Autodesk Fusion 360 part; units mm, degrees
(part 2 of 11)
  spline S15 degree 5 poles (4.403, 16.2127) (4.3927, 16.2052) (4.3722, 16.19) (4.3414, 16.1671) (4.3006, 16.1365) (4.2499, 16.098) (4.1996, 16.0592) (4.1496, 16.0202) (4.0999, 15.981) (4.0506, 15.9416) (4.0017, 15.9019) (3.9531, 15.8619) (3.9049, 15.8218) (3.857, 15.7814) (3.8095, 15.7408) (3.7624, 15.7) (3.7156, 15.6589) (3.6692, 15.6176) (3.6232, 15.5761) (3.5775, 15.5343) (3.5323, 15.4924) (3.4874, 15.4502) (3.443, 15.4078) (3.3989, 15.3651) (3.3552, 15.3223) (3.3119, 15.2792) (3.2691, 15.2359) (3.2266, 15.1924) (3.1846, 15.1487) (3.1429, 15.1048) (3.1017, 15.0607) (3.061, 15.0163) (3.0206, 14.9718) (2.9807, 14.927) (2.9412, 14.882) (2.9022, 14.8369) (2.8637, 14.7915) (2.8255, 14.7459) (2.7879, 14.7001) (2.7507, 14.6541) (2.714, 14.6079) (2.6778, 14.5615) (2.642, 14.5149) (2.6068, 14.4681) (2.5721, 14.4211) (2.5379, 14.3739) (2.5042, 14.3265) (2.471, 14.2789) (2.4383, 14.2311) (2.4062, 14.1831) (2.3746, 14.1349) (2.3436, 14.0866) (2.3132, 14.038) (2.2835, 13.9892) (2.2544, 13.9402) (2.2259, 13.891) (2.1979, 13.8417) (2.1705, 13.7921) (2.1437, 13.7424) (2.1175, 13.6925) (2.0921, 13.6424) (2.0677, 13.5921) (2.0442, 13.5415) (2.0218, 13.4906) (2.0002, 13.4395) (1.9793, 13.3882) (1.9589, 13.3369) (1.939, 13.2854) (1.9198, 13.2338) (1.9019, 13.1819) (1.8859, 13.1297) (1.8754, 13.0874) (1.8691, 13.0553) (1.8657, 13.0338) (1.8641, 13.023) knots -1 -1 -1 -1 -1 -1 -0.98571429 -0.97142857 -0.95714286 -0.94285714 -0.92857143 -0.91428571 -0.9 -0.88571429 -0.87142857 -0.85714286 -0.84285714 -0.82857143 -0.81428571 -0.8 -0.78571429 -0.77142857 -0.75714286 -0.74285714 -0.72857143 -0.71428571 -0.7 -0.68571429 -0.67142857 -0.65714286 -0.64285714 -0.62857143 -0.61428571 -0.6 -0.58571429 -0.57142857 -0.55714286 -0.54285714 -0.52857143 -0.51428571 -0.5 -0.48571429 -0.47142857 -0.45714286 -0.44285714 -0.42857143 -0.41428571 -0.4 -0.38571429 -0.37142857 -0.35714286 -0.34285714 -0.32857143 -0.31428571 -0.3 -0.28571429 -0.27142857 -0.25714286 -0.24285714 -0.22857143 -0.21428571 -0.2 -0.18571429 -0.17142857 -0.15714286 -0.14285714 -0.12857143 -0.11428571 -0.1 -0.08571429 -0.07142857 -0.05714286 -0.04285714 -0.02857143 -0.01428571 0 0 0 0 0 0
  line L15 (1.8641, 13.023) -> (1.6349, 11.4289)
  arc A31 (0.5894, 10.5728) -> (1.6349, 11.4289) centre (0.6451, 11.5712) ccw
  arc A32 (0.5894, 10.5728) -> (-0.5894, 10.5728) centre (0, 0) ccw
  arc A33 (-1.6349, 11.4289) -> (-0.5894, 10.5728) centre (-0.6451, 11.5712) ccw
  line L16 (-1.6349, 11.4289) -> (-1.8641, 13.023)
  spline S16 degree 5 poles (-1.8641, 13.023) (-1.8657, 13.0338) (-1.8691, 13.0553) (-1.8754, 13.0874) (-1.8859, 13.1297) (-1.9019, 13.1819) (-1.9198, 13.2338) (-1.939, 13.2854) (-1.9589, 13.3369) (-1.9793, 13.3882) (-2.0002, 13.4395) (-2.0218, 13.4906) (-2.0442, 13.5415) (-2.0677, 13.5921) (-2.0921, 13.6424) (-2.1175, 13.6925) (-2.1437, 13.7424) (-2.1705, 13.7921) (-2.1979, 13.8417) (-2.2259, 13.891) (-2.2544, 13.9402) (-2.2835, 13.9892) (-2.3132, 14.038) (-2.3436, 14.0866) (-2.3746, 14.1349) (-2.4062, 14.1831) (-2.4383, 14.2311) (-2.471, 14.2789) (-2.5042, 14.3265) (-2.5379, 14.3739) (-2.5721, 14.4211) (-2.6068, 14.4681) (-2.642, 14.5149) (-2.6778, 14.5615) (-2.714, 14.6079) (-2.7507, 14.6541) (-2.7879, 14.7001) (-2.8255, 14.7459) (-2.8637, 14.7915) (-2.9022, 14.8369) (-2.9412, 14.882) (-2.9807, 14.927) (-3.0206, 14.9718) (-3.061, 15.0163) (-3.1017, 15.0607) (-3.1429, 15.1048) (-3.1846, 15.1487) (-3.2266, 15.1924) (-3.2691, 15.2359) (-3.3119, 15.2792) (-3.3552, 15.3223) (-3.3989, 15.3651) (-3.443, 15.4078) (-3.4874, 15.4502) (-3.5323, 15.4924) (-3.5775, 15.5343) (-3.6232, 15.5761) (-3.6692, 15.6176) (-3.7156, 15.6589) (-3.7624, 15.7) (-3.8095, 15.7408) (-3.857, 15.7814) (-3.9049, 15.8218) (-3.9531, 15.8619) (-4.0017, 15.9019) (-4.0506, 15.9416) (-4.0999, 15.981) (-4.1496, 16.0202) (-4.1996, 16.0592) (-4.2499, 16.098) (-4.3006, 16.1365) (-4.3414, 16.1671) (-4.3722, 16.19) (-4.3927, 16.2052) (-4.403, 16.2127) knots 0 0 0 0 0 0 0.01428571 0.02857143 0.04285714 0.05714286 0.07142857 0.08571429 0.1 0.11428571 0.12857143 0.14285714 0.15714286 0.17142857 0.18571429 0.2 0.21428571 0.22857143 0.24285714 0.25714286 0.27142857 0.28571429 0.3 0.31428571 0.32857143 0.34285714 0.35714286 0.37142857 0.38571429 0.4 0.41428571 0.42857143 0.44285714 0.45714286 0.47142857 0.48571429 0.5 0.51428571 0.52857143 0.54285714 0.55714286 0.57142857 0.58571429 0.6 0.61428571 0.62857143 0.64285714 0.65714286 0.67142857 0.68571429 0.7 0.71428571 0.72857143 0.74285714 0.75714286 0.77142857 0.78571429 0.8 0.81428571 0.82857143 0.84285714 0.85714286 0.87142857 0.88571429 0.9 0.91428571 0.92857143 0.94285714 0.95714286 0.97142857 0.98571429 1 1 1 1 1 1
  arc A34 (-4.403, 16.2127) -> (-5.9675, 15.7044) centre (0, 0) ccw
  spline S17 degree 5 poles (-5.9675, 15.7044) (-5.9714, 15.6922) (-5.9791, 15.6679) (-5.9905, 15.6313) (-6.0055, 15.5825) (-6.0239, 15.5216) (-6.0419, 15.4606) (-6.0594, 15.3997) (-6.0765, 15.3388) (-6.0932, 15.2779) (-6.1095, 15.217) (-6.1253, 15.1562) (-6.1407, 15.0953) (-6.1557, 15.0345) (-6.1703, 14.9737) (-6.1844, 14.913) (-6.1981, 14.8523) (-6.2113, 14.7916) (-6.2242, 14.731) (-6.2365, 14.6704) (-6.2485, 14.6098) (-6.26, 14.5493) (-6.271, 14.4889) (-6.2816, 14.4285) (-6.2918, 14.3681) (-6.3015, 14.3079) (-6.3107, 14.2476) (-6.3195, 14.1875) (-6.3278, 14.1274) (-6.3357, 14.0674) (-6.3431, 14.0075) (-6.35, 13.9477) (-6.3565, 13.8879) (-6.3624, 13.8282) (-6.3679, 13.7686) (-6.3729, 13.7092) (-6.3775, 13.6498) (-6.3815, 13.5905) (-6.385, 13.5313) (-6.3881, 13.4722) (-6.3906, 13.4133) (-6.3927, 13.3545) (-6.3942, 13.2957) (-6.3952, 13.2372) (-6.3956, 13.1787) (-6.3956, 13.1204) (-6.395, 13.0623) (-6.3938, 13.0043) (-6.3922, 12.9464) (-6.39, 12.8887) (-6.3872, 12.8312) (-6.3839, 12.7738) (-6.3799, 12.7167) (-6.3752, 12.6597) (-6.37, 12.603) (-6.3642, 12.5464) (-6.3578, 12.49) (-6.3508, 12.4339) (-6.3433, 12.3779) (-6.3352, 12.3221) (-6.3262, 12.2667) (-6.3164, 12.2116) (-6.3057, 12.1568) (-6.2939, 12.1025) (-6.2813, 12.0484) (-6.2681, 11.9947) (-6.2544, 11.9412) (-6.2402, 11.8878) (-6.2255, 11.8348) (-6.2095, 11.7823) (-6.1917, 11.7307) (-6.1753, 11.6903) (-6.1615, 11.6606) (-6.1517, 11.6412) (-6.1466, 11.6315) knots -1 -1 -1 -1 -1 -1 -0.98571429 -0.97142857 -0.95714286 -0.94285714 -0.92857143 -0.91428571 -0.9 -0.88571429 -0.87142857 -0.85714286 -0.84285714 -0.82857143 -0.81428571 -0.8 -0.78571429 -0.77142857 -0.75714286 -0.74285714 -0.72857143 -0.71428571 -0.7 -0.68571429 -0.67142857 -0.65714286 -0.64285714 -0.62857143 -0.61428571 -0.6 -0.58571429 -0.57142857 -0.55714286 -0.54285714 -0.52857143 -0.51428571 -0.5 -0.48571429 -0.47142857 -0.45714286 -0.44285714 -0.42857143 -0.41428571 -0.4 -0.38571429 -0.37142857 -0.35714286 -0.34285714 -0.32857143 -0.31428571 -0.3 -0.28571429 -0.27142857 -0.25714286 -0.24285714 -0.22857143 -0.21428571 -0.2 -0.18571429 -0.17142857 -0.15714286 -0.14285714 -0.12857143 -0.11428571 -0.1 -0.08571429 -0.07142857 -0.05714286 -0.04285714 -0.02857143 -0.01428571 0 0 0 0 0 0
  line L17 (-6.1466, 11.6315) -> (-5.3951, 10.2071)
  arc A35 (-5.7377, 8.9) -> (-5.3951, 10.2071) centre (-6.2795, 9.7405) ccw
  arc A36 (-5.7377, 8.9) -> (-6.6914, 8.2071) centre (0, 0) ccw
  arc A37 (-8.0404, 8.2852) -> (-6.6914, 8.2071) centre (-7.3233, 8.9822) ccw
  line L18 (-8.0404, 8.2852) -> (-9.1628, 9.4401)
  spline S18 degree 5 poles (-9.1628, 9.4401) (-9.1704, 9.4479) (-9.1859, 9.4633) (-9.2098, 9.4855) (-9.2432, 9.5136) (-9.2868, 9.5465) (-9.3318, 9.5779) (-9.3777, 9.6084) (-9.424, 9.6383) (-9.4707, 9.6679) (-9.5177, 9.6971) (-9.5652, 9.7257) (-9.6133, 9.7537) (-9.662, 9.7809) (-9.7114, 9.8072) (-9.7614, 9.8328) (-9.8119, 9.8578) (-9.8628, 9.8823) (-9.9141, 9.9062) (-9.9657, 9.9297) (-10.0177, 9.9528) (-10.07, 9.9753) (-10.1228, 9.9973) (-10.1759, 10.0187) (-10.2294, 10.0397) (-10.2833, 10.0601) (-10.3375, 10.08) (-10.392, 10.0994) (-10.4468, 10.1184) (-10.5019, 10.137) (-10.5574, 10.1551) (-10.6131, 10.1727) (-10.6691, 10.1898) (-10.7254, 10.2065) (-10.782, 10.2228) (-10.8388, 10.2386) (-10.8959, 10.2539) (-10.9533, 10.2689) (-11.011, 10.2833) (-11.0688, 10.2974) (-11.127, 10.311) (-11.1853, 10.3242) (-11.2439, 10.337) (-11.3027, 10.3493) (-11.3618, 10.3612) (-11.4211, 10.3727) (-11.4806, 10.3837) (-11.5403, 10.3944) (-11.6002, 10.4046) (-11.6603, 10.4144) (-11.7206, 10.4238) (-11.7812, 10.4328) (-11.8419, 10.4414) (-11.9028, 10.4496) (-11.9639, 10.4573) (-12.0251, 10.4647) (-12.0866, 10.4716) (-12.1482, 10.4782) (-12.21, 10.4843) (-12.272, 10.4901) (-12.3341, 10.4954) (-12.3965, 10.5003) (-12.4589, 10.5049) (-12.5215, 10.509) (-12.5843, 10.5128) (-12.6472, 10.5161) (-12.7103, 10.519) (-12.7735, 10.5216) (-12.8369, 10.5237) (-12.9004, 10.5255) (-12.964, 10.5269) (-13.0151, 10.5277) (-13.0534, 10.5281) (-13.079, 10.5283) (-13.0918, 10.5283) knots 0 0 0 0 0 0 0.01428571 0.02857143 0.04285714 0.05714286 0.07142857 0.08571429 0.1 0.11428571 0.12857143 0.14285714 0.15714286 0.17142857 0.18571429 0.2 0.21428571 0.22857143 0.24285714 0.25714286 0.27142857 0.28571429 0.3 0.31428571 0.32857143 0.34285714 0.35714286 0.37142857 0.38571429 0.4 0.41428571 0.42857143 0.44285714 0.45714286 0.47142857 0.48571429 0.5 0.51428571 0.52857143 0.54285714 0.55714286 0.57142857 0.58571429 0.6 0.61428571 0.62857143 0.64285714 0.65714286 0.67142857 0.68571429 0.7 0.71428571 0.72857143 0.74285714 0.75714286 0.77142857 0.78571429 0.8 0.81428571 0.82857143 0.84285714 0.85714286 0.87142857 0.88571429 0.9 0.91428571 0.92857143 0.94285714 0.95714286 0.97142857 0.98571429 1 1 1 1 1 1
  arc A38 (-13.0918, 10.5283) -> (-14.0586, 9.1976) centre (0, 0) ccw
  spline S19 degree 5 poles (-14.0586, 9.1976) (-14.0546, 9.1854) (-14.0465, 9.1611) (-14.0343, 9.1248) (-14.0178, 9.0765) (-13.9968, 9.0164) (-13.9755, 8.9566) (-13.9539, 8.897) (-13.9319, 8.8377) (-13.9096, 8.7786) (-13.887, 8.7198) (-13.864, 8.6612) (-13.8407, 8.603) (-13.8171, 8.5449) (-13.7932, 8.4872) (-13.7689, 8.4298) (-13.7443, 8.3726) (-13.7194, 8.3157) (-13.6941, 8.2591) (-13.6685, 8.2028) (-13.6426, 8.1468) (-13.6163, 8.0911) (-13.5897, 8.0357) (-13.5628, 7.9806) (-13.5355, 7.9258) (-13.508, 7.8714) (-13.48, 7.8172) (-13.4518, 7.7634) (-13.4232, 7.7099) (-13.3943, 7.6568) (-13.3651, 7.6039) (-13.3355, 7.5514) (-13.3056, 7.4993) (-13.2753, 7.4475) (-13.2448, 7.3961) (-13.2139, 7.345) (-13.1826, 7.2943) (-13.151, 7.244) (-13.1191, 7.194) (-13.0869, 7.1444) (-13.0543, 7.0952) (-13.0213, 7.0465) (-12.988, 6.9981) (-12.9544, 6.9501) (-12.9204, 6.9026) (-12.8861, 6.8554) (-12.8515, 6.8087) (-12.8164, 6.7625) (-12.7811, 6.7166) (-12.7454, 6.6712) (-12.7093, 6.6263) (-12.6729, 6.5819) (-12.6361, 6.538) (-12.5989, 6.4946) (-12.5613, 6.4518) (-12.5233, 6.4095) (-12.485, 6.3677) (-12.4464, 6.3263) (-12.4074, 6.2854) (-12.368, 6.2451) (-12.3282, 6.2055) (-12.2879, 6.1667) (-12.247, 6.1287) (-12.2055, 6.0916) (-12.1636, 6.0553) (-12.1213, 6.0196) (-12.0788, 5.9844) (-12.036, 5.9495) (-11.9928, 5.9153) (-11.9491, 5.8822) (-11.9043, 5.8509) (-11.8673, 5.8279) (-11.8387, 5.812) (-11.8193, 5.802) (-11.8095, 5.7972) knots -1 -1 -1 -1 -1 -1 -0.98571429 -0.97142857 -0.95714286 -0.94285714 -0.92857143 -0.91428571 -0.9 -0.88571429 -0.87142857 -0.85714286 -0.84285714 -0.82857143 -0.81428571 -0.8 -0.78571429 -0.77142857 -0.75714286 -0.74285714 -0.72857143 -0.71428571 -0.7 -0.68571429 -0.67142857 -0.65714286 -0.64285714 -0.62857143 -0.61428571 -0.6 -0.58571429 -0.57142857 -0.55714286 -0.54285714 -0.52857143 -0.51428571 -0.5 -0.48571429 -0.47142857 -0.45714286 -0.44285714 -0.42857143 -0.41428571 -0.4 -0.38571429 -0.37142857 -0.35714286 -0.34285714 -0.32857143 -0.31428571 -0.3 -0.28571429 -0.27142857 -0.25714286 -0.24285714 -0.22857143 -0.21428571 -0.2 -0.18571429 -0.17142857 -0.15714286 -0.14285714 -0.12857143 -0.11428571 -0.1 -0.08571429 -0.07142857 -0.05714286 -0.04285714 -0.02857143 -0.01428571 0 0 0 0 0 0
  line L19 (-11.8095, 5.7972) -> (-10.3643, 5.0866)
  arc A39 (-9.8732, 3.8277) -> (-10.3643, 5.0866) centre (-10.8056, 4.1892) ccw
  circle A40 centre (0, 0) radius 4
  dimension "d17" = 8
  constraint coincident A0.centre A2.centre
  measures "d17" diameter of A40
extrude "Extrude3" add sketch "Sketch1 (3)" along normal blind 19 contours A40 bodies 1 in component "Spur Gear (10 teeth)"
sketch "Sketch2 (3)" plane through (0, 0, -12) normal (0, 0, 1) x (1, 0, 0)
  circle A0 centre (0, 0) radius 4
  dimension "d20" = 8
  constraint coincident A0.centre origin
  measures "d20" diameter of A0
extrude "Extrude3'" add sketch "Sketch2 (3)" against normal blind 19 sketch seen with x (1, 0, 0) y (0, 1, 0) z (0, 0, 1) at (0, 0, 12) bodies 2 in component "Spur Gear (28 teeth)"
delete_face "DeleteFace1" 1 faces at (3.9801, -0.3983, -12.6667) on bodies 2 in component "Spur Gear (28 teeth)"
sketch "Sketch3 (3)" plane through (0, 0, -12) normal (0, 0, -1) x (1, 0, 0)
  arc A0 (34.1816, 13.5652) -> (33.6119, 12.2925) centre (34.5511, 12.636) ccw
  line L0 (34.1816, 13.5652) -> (34.2383, 13.5877)
  spline S0 degree 5 poles (34.2383, 13.5877) (34.2524, 13.5933) (34.2804, 13.6049) (34.322, 13.6232) (34.3766, 13.6494) (34.4436, 13.6848) (34.5098, 13.722) (34.5755, 13.7604) (34.6409, 13.7995) (34.7062, 13.8389) (34.7712, 13.8788) (34.8359, 13.9193) (34.9003, 13.9605) (34.9642, 14.0026) (35.0278, 14.0456) (35.0909, 14.0894) (35.1536, 14.134) (35.2161, 14.1791) (35.2782, 14.2247) (35.3402, 14.2708) (35.4019, 14.3173) (35.4633, 14.3644) (35.5244, 14.412) (35.5852, 14.4601) (35.6458, 14.5087) (35.7061, 14.5579) (35.7661, 14.6075) (35.8258, 14.6576) (35.8853, 14.7082) (35.9446, 14.7592) (36.0036, 14.8106) (36.0624, 14.8624) (36.1209, 14.9146) (36.1791, 14.9673) (36.2372, 15.0204) (36.295, 15.0739) (36.3525, 15.1278) (36.4098, 15.182) (36.4669, 15.2367) (36.5237, 15.2917) (36.5803, 15.3472) (36.6367, 15.4029) (36.6928, 15.4591) (36.7487, 15.5156) (36.8044, 15.5725) (36.8598, 15.6297) (36.9151, 15.6872) (36.9701, 15.7452) (37.0248, 15.8034) (37.0794, 15.862) (37.1337, 15.9209) (37.1878, 15.9802) (37.2417, 16.0398) (37.2954, 16.0997) (37.3488, 16.1599) (37.402, 16.2204) (37.455, 16.2813) (37.5078, 16.3425) (37.5604, 16.404) (37.6127, 16.4657) (37.6648, 16.5278) (37.7168, 16.5902) (37.7684, 16.6529) (37.8199, 16.7159) (37.8712, 16.7792) (37.9222, 16.8427) (37.9731, 16.9066) (38.0237, 16.9707) (38.0741, 17.0352) (38.1243, 17.0999) (38.1742, 17.1648) (38.214, 17.2171) (38.2438, 17.2563) (38.2636, 17.2826) (38.2735, 17.2957) knots 0 0 0 0 0 0 0.01428571 0.02857143 0.04285714 0.05714286 0.07142857 0.08571429 0.1 0.11428571 0.12857143 0.14285714 0.15714286 0.17142857 0.18571429 0.2 0.21428571 0.22857143 0.24285714 0.25714286 0.27142857 0.28571429 0.3 0.31428571 0.32857143 0.34285714 0.35714286 0.37142857 0.38571429 0.4 0.41428571 0.42857143 0.44285714 0.45714286 0.47142857 0.48571429 0.5 0.51428571 0.52857143 0.54285714 0.55714286 0.57142857 0.58571429 0.6 0.61428571 0.62857143 0.64285714 0.65714286 0.67142857 0.68571429 0.7 0.71428571 0.72857143 0.74285714 0.75714286 0.77142857 0.78571429 0.8 0.81428571 0.82857143 0.84285714 0.85714286 0.87142857 0.88571429 0.9 0.91428571 0.92857143 0.94285714 0.95714286 0.97142857 0.98571429 1 1 1 1 1 1
  arc A1 (38.2735, 17.2957) -> (37.3855, 19.1397) centre (0, 0) ccw
  spline S1 degree 5 poles (31.9705, 18.2968) (31.9837, 18.3043) (32.0102, 18.319) (32.0504, 18.3401) (32.105, 18.3664) (32.1744, 18.3968) (32.2448, 18.4253) (32.3158, 18.4528) (32.3871, 18.4796) (32.4586, 18.5059) (32.5304, 18.5319) (32.6024, 18.5573) (32.6748, 18.5819) (32.7475, 18.6056) (32.8208, 18.6285) (32.8944, 18.6505) (32.9683, 18.6718) (33.0425, 18.6925) (33.1169, 18.7127) (33.1916, 18.7324) (33.2664, 18.7516) (33.3415, 18.7703) (33.4168, 18.7884) (33.4924, 18.806) (33.5682, 18.823) (33.6442, 18.8394) (33.7204, 18.8554) (33.7969, 18.8709) (33.8735, 18.8859) (33.9503, 18.9004) (34.0272, 18.9145) (34.1044, 18.9281) (34.1817, 18.9413) (34.2592, 18.954) (34.3369, 18.9663) (34.4148, 18.9781) (34.4928, 18.9895) (34.5709, 19.0005) (34.6492, 19.011) (34.7277, 19.0211) (34.8063, 19.0308) (34.8851, 19.0401) (34.964, 19.049) (35.043, 19.0575) (35.1222, 19.0656) (35.2015, 19.0732) (35.281, 19.0805) (35.3605, 19.0874) (35.4402, 19.0939) (35.52, 19.1) (35.6, 19.1058) (35.68, 19.1111) (35.7602, 19.1161) (35.8405, 19.1207) (35.9209, 19.1249) (36.0014, 19.1288) (36.0821, 19.1323) (36.1628, 19.1354) (36.2436, 19.1382) (36.3246, 19.1406) (36.4056, 19.1426) (36.4868, 19.1443) (36.568, 19.1456) (36.6493, 19.1466) (36.7308, 19.1472) (36.8123, 19.1475) (36.8939, 19.1474) (36.9756, 19.147) (37.0574, 19.1463) (37.1393, 19.1452) (37.2212, 19.1437) (37.2869, 19.1423) (37.3362, 19.141) (37.369, 19.1402) (37.3855, 19.1397) knots 0 0 0 0 0 0 0.01428571 0.02857143 0.04285714 0.05714286 0.07142857 0.08571429 0.1 0.11428571 0.12857143 0.14285714 0.15714286 0.17142857 0.18571429 0.2 0.21428571 0.22857143 0.24285714 0.25714286 0.27142857 0.28571429 0.3 0.31428571 0.32857143 0.34285714 0.35714286 0.37142857 0.38571429 0.4 0.41428571 0.42857143 0.44285714 0.45714286 0.47142857 0.48571429 0.5 0.51428571 0.52857143 0.54285714 0.55714286 0.57142857 0.58571429 0.6 0.61428571 0.62857143 0.64285714 0.65714286 0.67142857 0.68571429 0.7 0.71428571 0.72857143 0.74285714 0.75714286 0.77142857 0.78571429 0.8 0.81428571 0.82857143 0.84285714 0.85714286 0.87142857 0.88571429 0.9 0.91428571 0.92857143 0.94285714 0.95714286 0.97142857 0.98571429 1 1 1 1 1 1
  line L1 (31.9705, 18.2968) -> (31.9176, 18.2665)
  arc A2 (30.5673, 18.6146) -> (31.9176, 18.2665) centre (31.4214, 19.1347) ccw
  arc A3 (30.5673, 18.6146) -> (30.0339, 19.4636) centre (0, 0) ccw
  arc A4 (30.3061, 20.8312) -> (30.0339, 19.4636) centre (30.8731, 20.0075) ccw
  line L2 (30.3061, 20.8312) -> (30.3563, 20.8658)
  spline S2 degree 5 poles (30.3563, 20.8658) (30.3688, 20.8744) (30.3936, 20.8919) (30.43, 20.919) (30.4774, 20.9567) (30.5349, 21.0061) (30.5912, 21.0571) (30.6467, 21.1092) (30.7017, 21.1618) (30.7566, 21.2148) (30.8111, 21.2682) (30.8652, 21.322) (30.9188, 21.3765) (30.9717, 21.4318) (31.0241, 21.4879) (31.0759, 21.5446) (31.1271, 21.602) (31.178, 21.6599) (31.2284, 21.7182) (31.2786, 21.7769) (31.3284, 21.836) (31.3778, 21.8955) (31.4268, 21.9555) (31.4754, 22.016) (31.5236, 22.0769) (31.5714, 22.1382) (31.6189, 22.2) (31.666, 22.2621) (31.7127, 22.3247) (31.7592, 22.3875) (31.8053, 22.4508) (31.851, 22.5144) (31.8964, 22.5783) (31.9415, 22.6427) (31.9863, 22.7073) (32.0307, 22.7723) (32.0748, 22.8377) (32.1186, 22.9033) (32.1621, 22.9693) (32.2052, 23.0356) (32.2481, 23.1023) (32.2906, 23.1692) (32.3329, 23.2364) (32.3748, 23.3039) (32.4164, 23.3718) (32.4578, 23.4399) (32.4988, 23.5083) (32.5395, 23.577) (32.58, 23.646) (32.6201, 23.7153) (32.66, 23.7848) (32.6995, 23.8546) (32.7388, 23.9247) (32.7778, 23.995) (32.8165, 24.0656) (32.8549, 24.1365) (32.893, 24.2076) (32.9309, 24.279) (32.9684, 24.3506) (33.0057, 24.4225) (33.0427, 24.4947) (33.0794, 24.567) (33.1159, 24.6397) (33.1521, 24.7125) (33.188, 24.7856) (33.2236, 24.8589) (33.2589, 24.9325) (33.294, 25.0063) (33.3288, 25.0803) (33.3633, 25.1546) (33.3976, 25.229) (33.4248, 25.2888) (33.445, 25.3337) (33.4585, 25.3637) (33.4652, 25.3787) knots 0 0 0 0 0 0 0.01428571 0.02857143 0.04285714 0.05714286 0.07142857 0.08571429 0.1 0.11428571 0.12857143 0.14285714 0.15714286 0.17142857 0.18571429 0.2 0.21428571 0.22857143 0.24285714 0.25714286 0.27142857 0.28571429 0.3 0.31428571 0.32857143 0.34285714 0.35714286 0.37142857 0.38571429 0.4 0.41428571 0.42857143 0.44285714 0.45714286 0.47142857 0.48571429 0.5 0.51428571 0.52857143 0.54285714 0.55714286 0.57142857 0.58571429 0.6 0.61428571 0.62857143 0.64285714 0.65714286 0.67142857 0.68571429 0.7 0.71428571 0.72857143 0.74285714 0.75714286 0.77142857 0.78571429 0.8 0.81428571 0.82857143 0.84285714 0.85714286 0.87142857 0.88571429 0.9 0.91428571 0.92857143 0.94285714 0.95714286 0.97142857 0.98571429 1 1 1 1 1 1
  arc A5 (33.4652, 25.3787) -> (32.1891, 26.9789) centre (0, 0) ccw
  spline S3 degree 5 poles (27.0976, 24.9521) (27.1087, 24.9624) (27.1313, 24.9826) (27.1658, 25.0122) (27.2131, 25.05) (27.2741, 25.095) (27.3364, 25.1385) (27.3995, 25.1811) (27.463, 25.223) (27.5269, 25.2647) (27.591, 25.306) (27.6556, 25.3467) (27.7207, 25.3868) (27.7864, 25.4262) (27.8526, 25.4647) (27.9195, 25.5026) (27.9868, 25.5398) (28.0546, 25.5765) (28.1226, 25.6127) (28.191, 25.6485) (28.2597, 25.6839) (28.3288, 25.7188) (28.3982, 25.7533) (28.4679, 25.7872) (28.538, 25.8207) (28.6085, 25.8536) (28.6793, 25.8862) (28.7503, 25.9182) (28.8217, 25.9499) (28.8933, 25.9812) (28.9652, 26.0121) (29.0374, 26.0425) (29.1099, 26.0726) (29.1826, 26.1022) (29.2556, 26.1315) (29.3289, 26.1603) (29.4024, 26.1888) (29.4762, 26.2168) (29.5502, 26.2445) (29.6244, 26.2719) (29.6989, 26.2988) (29.7736, 26.3254) (29.8486, 26.3516) (29.9237, 26.3775) (29.9991, 26.403) (30.0747, 26.4281) (30.1506, 26.4529) (30.2266, 26.4773) (30.3029, 26.5014) (30.3793, 26.5251) (30.456, 26.5485) (30.5328, 26.5715) (30.6099, 26.5942) (30.6872, 26.6166) (30.7646, 26.6386) (30.8422, 26.6603) (30.9201, 26.6816) (30.9981, 26.7026) (31.0763, 26.7233) (31.1547, 26.7437) (31.2332, 26.7637) (31.312, 26.7834) (31.3909, 26.8028) (31.4699, 26.8218) (31.5492, 26.8405) (31.6286, 26.859) (31.7082, 26.877) (31.7879, 26.8948) (31.8679, 26.9123) (31.9479, 26.9294) (32.0282, 26.9462) (32.0925, 26.9594) (32.1408, 26.9692) (32.173, 26.9757) (32.1891, 26.9789) knots 0 0 0 0 0 0 0.01428571 0.02857143 0.04285714 0.05714286 0.07142857 0.08571429 0.1 0.11428571 0.12857143 0.14285714 0.15714286 0.17142857 0.18571429 0.2 0.21428571 0.22857143 0.24285714 0.25714286 0.27142857 0.28571429 0.3 0.31428571 0.32857143 0.34285714 0.35714286 0.37142857 0.38571429 0.4 0.41428571 0.42857143 0.44285714 0.45714286 0.47142857 0.48571429 0.5 0.51428571 0.52857143 0.54285714 0.55714286 0.57142857 0.58571429 0.6 0.61428571 0.62857143 0.64285714 0.65714286 0.67142857 0.68571429 0.7 0.71428571 0.72857143 0.74285714 0.75714286 0.77142857 0.78571429 0.8 0.81428571 0.82857143 0.84285714 0.85714286 0.87142857 0.88571429 0.9 0.91428571 0.92857143 0.94285714 0.95714286 0.97142857 0.98571429 1 1 1 1 1 1
  line L3 (27.0976, 24.9521) -> (27.0527, 24.9108)
  arc A6 (25.6588, 24.9498) -> (27.0527, 24.9108) centre (26.3758, 25.6469) ccw
  arc A7 (25.6588, 24.9498) -> (24.9498, 25.6588) centre (0, 0) ccw
  arc A8 (24.9108, 27.0527) -> (24.9498, 25.6588) centre (25.6469, 26.3758) ccw
  line L4 (24.9108, 27.0527) -> (24.9521, 27.0976)
  spline S4 degree 5 poles (24.9521, 27.0976) (24.9624, 27.1087) (24.9826, 27.1313) (25.0122, 27.1658) (25.05, 27.2131) (25.095, 27.2741) (25.1385, 27.3364) (25.1811, 27.3995) (25.223, 27.463) (25.2647, 27.5269) (25.306, 27.591) (25.3467, 27.6556) (25.3868, 27.7207) (25.4262, 27.7864) (25.4647, 27.8526) (25.5026, 27.9195) (25.5398, 27.9868) (25.5765, 28.0546) (25.6127, 28.1226) (25.6485, 28.191) (25.6839, 28.2597) (25.7188, 28.3288) (25.7533, 28.3982) (25.7872, 28.4679) (25.8207, 28.538) (25.8536, 28.6085) (25.8862, 28.6793) (25.9182, 28.7503) (25.9499, 28.8217) (25.9812, 28.8933) (26.0121, 28.9652) (26.0425, 29.0374) (26.0726, 29.1099) (26.1022, 29.1826) (26.1315, 29.2556) (26.1603, 29.3289) (26.1888, 29.4024) (26.2168, 29.4762) (26.2445, 29.5502) (26.2719, 29.6244) (26.2988, 29.6989) (26.3254, 29.7736) (26.3516, 29.8486) (26.3775, 29.9237) (26.403, 29.9991) (26.4281, 30.0747) (26.4529, 30.1506) (26.4773, 30.2266) (26.5014, 30.3029) (26.5251, 30.3793) (26.5485, 30.456) (26.5715, 30.5328) (26.5942, 30.6099) (26.6166, 30.6872) (26.6386, 30.7646) (26.6603, 30.8422) (26.6816, 30.9201) (26.7026, 30.9981) (26.7233, 31.0763) (26.7437, 31.1547) (26.7637, 31.2332) (26.7834, 31.312) (26.8028, 31.3909) (26.8218, 31.4699) (26.8405, 31.5492) (26.859, 31.6286) (26.877, 31.7082) (26.8948, 31.7879) (26.9123, 31.8679) (26.9294, 31.9479) (26.9462, 32.0282) (26.9594, 32.0925) (26.9692, 32.1408) (26.9757, 32.173) (26.9789, 32.1891) knots 0 0 0 0 0 0 0.01428571 0.02857143 0.04285714 0.05714286 0.07142857 0.08571429 0.1 0.11428571 0.12857143 0.14285714 0.15714286 0.17142857 0.18571429 0.2 0.21428571 0.22857143 0.24285714 0.25714286 0.27142857 0.28571429 0.3 0.31428571 0.32857143 0.34285714 0.35714286 0.37142857 0.38571429 0.4 0.41428571 0.42857143 0.44285714 0.45714286 0.47142857 0.48571429 0.5 0.51428571 0.52857143 0.54285714 0.55714286 0.57142857 0.58571429 0.6 0.61428571 0.62857143 0.64285714 0.65714286 0.67142857 0.68571429 0.7 0.71428571 0.72857143 0.74285714 0.75714286 0.77142857 0.78571429 0.8 0.81428571 0.82857143 0.84285714 0.85714286 0.87142857 0.88571429 0.9 0.91428571 0.92857143 0.94285714 0.95714286 0.97142857 0.98571429 1 1 1 1 1 1
  arc A9 (26.9789, 32.1891) -> (25.3787, 33.4652) centre (0, 0) ccw
  spline S5 degree 5 poles (20.8658, 30.3563) (20.8744, 30.3688) (20.8919, 30.3936) (20.919, 30.43) (20.9567, 30.4774) (21.0061, 30.5349) (21.0571, 30.5912) (21.1092, 30.6467) (21.1618, 30.7017) (21.2148, 30.7566) (21.2682, 30.8111) (21.322, 30.8652) (21.3765, 30.9188) (21.4318, 30.9717) (21.4879, 31.0241) (21.5446, 31.0759) (21.602, 31.1271) (21.6599, 31.178) (21.7182, 31.2284) (21.7769, 31.2786) (21.836, 31.3284) (21.8955, 31.3778) (21.9555, 31.4268) (22.016, 31.4754) (22.0769, 31.5236) (22.1382, 31.5714) (22.2, 31.6189) (22.2621, 31.666) (22.3247, 31.7127) (22.3875, 31.7592) (22.4508, 31.8053) (22.5144, 31.851) (22.5783, 31.8964) (22.6427, 31.9415) (22.7073, 31.9863) (22.7723, 32.0307) (22.8377, 32.0748) (22.9033, 32.1186) (22.9693, 32.1621) (23.0356, 32.2052) (23.1023, 32.2481) (23.1692, 32.2906) (23.2364, 32.3329) (23.3039, 32.3748) (23.3718, 32.4164) (23.4399, 32.4578) (23.5083, 32.4988) (23.577, 32.5395) (23.646, 32.58) (23.7153, 32.6201) (23.7848, 32.66) (23.8546, 32.6995) (23.9247, 32.7388) (23.995, 32.7778) (24.0656, 32.8165) (24.1365, 32.8549) (24.2076, 32.893) (24.279, 32.9309) (24.3506, 32.9684) (24.4225, 33.0057) (24.4947, 33.0427) (24.567, 33.0794) (24.6397, 33.1159) (24.7125, 33.1521) (24.7856, 33.188) (24.8589, 33.2236) (24.9325, 33.2589) (25.0063, 33.294) (25.0803, 33.3288) (25.1546, 33.3633) (25.229, 33.3976) (25.2888, 33.4248) (25.3337, 33.445) (25.3637, 33.4585) (25.3787, 33.4652) knots 0 0 0 0 0 0 0.01428571 0.02857143 0.04285714 0.05714286 0.07142857 0.08571429 0.1 0.11428571 0.12857143 0.14285714 0.15714286 0.17142857 0.18571429 0.2 0.21428571 0.22857143 0.24285714 0.25714286 0.27142857 0.28571429 0.3 0.31428571 0.32857143 0.34285714 0.35714286 0.37142857 0.38571429 0.4 0.41428571 0.42857143 0.44285714 0.45714286 0.47142857 0.48571429 0.5 0.51428571 0.52857143 0.54285714 0.55714286 0.57142857 0.58571429 0.6 0.61428571 0.62857143 0.64285714 0.65714286 0.67142857 0.68571429 0.7 0.71428571 0.72857143 0.74285714 0.75714286 0.77142857 0.78571429 0.8 0.81428571 0.82857143 0.84285714 0.85714286 0.87142857 0.88571429 0.9 0.91428571 0.92857143 0.94285714 0.95714286 0.97142857 0.98571429 1 1 1 1 1 1
  line L5 (20.8658, 30.3563) -> (20.8312, 30.3061)
  arc A10 (19.4636, 30.0339) -> (20.8312, 30.3061) centre (20.0075, 30.8731) ccw
  arc A11 (19.4636, 30.0339) -> (18.6146, 30.5673) centre (0, 0) ccw
  arc A12 (18.2665, 31.9176) -> (18.6146, 30.5673) centre (19.1347, 31.4214) ccw
  line L6 (18.2665, 31.9176) -> (18.2968, 31.9705)
  spline S6 degree 5 poles (18.2968, 31.9705) (18.3043, 31.9837) (18.319, 32.0102) (18.3401, 32.0504) (18.3664, 32.105) (18.3968, 32.1744) (18.4253, 32.2448) (18.4528, 32.3158) (18.4796, 32.3871) (18.5059, 32.4586) (18.5319, 32.5304) (18.5573, 32.6024) (18.5819, 32.6748) (18.6056, 32.7475) (18.6285, 32.8208) (18.6505, 32.8944) (18.6718, 32.9683) (18.6925, 33.0425) (18.7127, 33.1169) (18.7324, 33.1916) (18.7516, 33.2664) (18.7703, 33.3415) (18.7884, 33.4168) (18.806, 33.4924) (18.823, 33.5682) (18.8394, 33.6442) (18.8554, 33.7204) (18.8709, 33.7969) (18.8859, 33.8735) (18.9004, 33.9503) (18.9145, 34.0272) (18.9281, 34.1044) (18.9413, 34.1817) (18.954, 34.2592) (18.9663, 34.3369) (18.9781, 34.4148) (18.9895, 34.4928) (19.0005, 34.5709) (19.011, 34.6492) (19.0211, 34.7277) (19.0308, 34.8063) (19.0401, 34.8851) (19.049, 34.964) (19.0575, 35.043) (19.0656, 35.1222) (19.0732, 35.2015) (19.0805, 35.281) (19.0874, 35.3605) (19.0939, 35.4402) (19.1, 35.52) (19.1058, 35.6) (19.1111, 35.68) (19.1161, 35.7602) (19.1207, 35.8405) (19.1249, 35.9209) (19.1288, 36.0014) (19.1323, 36.0821) (19.1354, 36.1628) (19.1382, 36.2436) (19.1406, 36.3246) (19.1426, 36.4056) (19.1443, 36.4868) (19.1456, 36.568) (19.1466, 36.6493) (19.1472, 36.7308) (19.1475, 36.8123) (19.1474, 36.8939) (19.147, 36.9756) (19.1463, 37.0574) (19.1452, 37.1393) (19.1437, 37.2212) (19.1423, 37.2869) (19.141, 37.3362) (19.1402, 37.369) (19.1397, 37.3855) knots 0 0 0 0 0 0 0.01428571 0.02857143 0.04285714 0.05714286 0.07142857 0.08571429 0.1 0.11428571 0.12857143 0.14285714 0.15714286 0.17142857 0.18571429 0.2 0.21428571 0.22857143 0.24285714 0.25714286 0.27142857 0.28571429 0.3 0.31428571 0.32857143 0.34285714 0.35714286 0.37142857 0.38571429 0.4 0.41428571 0.42857143 0.44285714 0.45714286 0.47142857 0.48571429 0.5 0.51428571 0.52857143 0.54285714 0.55714286 0.57142857 0.58571429 0.6 0.61428571 0.62857143 0.64285714 0.65714286 0.67142857 0.68571429 0.7 0.71428571 0.72857143 0.74285714 0.75714286 0.77142857 0.78571429 0.8 0.81428571 0.82857143 0.84285714 0.85714286 0.87142857 0.88571429 0.9 0.91428571 0.92857143 0.94285714 0.95714286 0.97142857 0.98571429 1 1 1 1 1 1
  arc A13 (19.1397, 37.3855) -> (17.2957, 38.2735) centre (0, 0) ccw
  spline S7 degree 5 poles (13.5877, 34.2383) (13.5933, 34.2524) (13.6049, 34.2804) (13.6232, 34.322) (13.6494, 34.3766) (13.6848, 34.4436) (13.722, 34.5098) (13.7604, 34.5755) (13.7995, 34.6409) (13.8389, 34.7062) (13.8788, 34.7712) (13.9193, 34.8359) (13.9605, 34.9003) (14.0026, 34.9642) (14.0456, 35.0278) (14.0894, 35.0909) (14.134, 35.1536) (14.1791, 35.2161) (14.2247, 35.2782) (14.2708, 35.3402) (14.3173, 35.4019) (14.3644, 35.4633) (14.412, 35.5244) (14.4601, 35.5852) (14.5087, 35.6458) (14.5579, 35.7061) (14.6075, 35.7661) (14.6576, 35.8258) (14.7082, 35.8853) (14.7592, 35.9446) (14.8106, 36.0036) (14.8624, 36.0624) (14.9146, 36.1209) (14.9673, 36.1791) (15.0204, 36.2372) (15.0739, 36.295) (15.1278, 36.3525) (15.182, 36.4098) (15.2367, 36.4669) (15.2917, 36.5237) (15.3472, 36.5803) (15.4029, 36.6367) (15.4591, 36.6928) (15.5156, 36.7487) (15.5725, 36.8044) (15.6297, 36.8598) (15.6872, 36.9151) (15.7452, 36.9701) (15.8034, 37.0248) (15.862, 37.0794) (15.9209, 37.1337) (15.9802, 37.1878) (16.0398, 37.2417) (16.0997, 37.2954) (16.1599, 37.3488) (16.2204, 37.402) (16.2813, 37.455) (16.3425, 37.5078) (16.404, 37.5604) (16.4657, 37.6127) (16.5278, 37.6648) (16.5902, 37.7168) (16.6529, 37.7684) (16.7159, 37.8199) (16.7792, 37.8712) (16.8427, 37.9222) (16.9066, 37.9731) (16.9707, 38.0237) (17.0352, 38.0741) (17.0999, 38.1243) (17.1648, 38.1742) (17.2171, 38.214) (17.2563, 38.2438) (17.2826, 38.2636) (17.2957, 38.2735) knots 0 0 0 0 0 0 0.01428571 0.02857143 0.04285714 0.05714286 0.07142857 0.08571429 0.1 0.11428571 0.12857143 0.14285714 0.15714286 0.17142857 0.18571429 0.2 0.21428571 0.22857143 0.24285714 0.25714286 0.27142857 0.28571429 0.3 0.31428571 0.32857143 0.34285714 0.35714286 0.37142857 0.38571429 0.4 0.41428571 0.42857143 0.44285714 0.45714286 0.47142857 0.48571429 0.5 0.51428571 0.52857143 0.54285714 0.55714286 0.57142857 0.58571429 0.6 0.61428571 0.62857143 0.64285714 0.65714286 0.67142857 0.68571429 0.7 0.71428571 0.72857143 0.74285714 0.75714286 0.77142857 0.78571429 0.8 0.81428571 0.82857143 0.84285714 0.85714286 0.87142857 0.88571429 0.9 0.91428571 0.92857143 0.94285714 0.95714286 0.97142857 0.98571429 1 1 1 1 1 1
  line L7 (13.5877, 34.2383) -> (13.5652, 34.1816)
  arc A14 (12.2925, 33.6119) -> (13.5652, 34.1816) centre (12.636, 34.5511) ccw
  arc A15 (12.2925, 33.6119) -> (11.346, 33.9431) centre (0, 0) ccw
  arc A16 (10.7062, 35.182) -> (11.346, 33.9431) centre (11.6631, 34.8915) ccw
  line L8 (10.7062, 35.182) -> (10.7239, 35.2404)
  spline S8 degree 5 poles (10.7239, 35.2404) (10.7283, 35.2549) (10.7368, 35.284) (10.7484, 35.3279) (10.7619, 35.3869) (10.7761, 35.4614) (10.7882, 35.5364) (10.7992, 35.6117) (10.8094, 35.6872) (10.8192, 35.7628) (10.8286, 35.8385) (10.8373, 35.9144) (10.8452, 35.9904) (10.8522, 36.0666) (10.8581, 36.1431) (10.8632, 36.2198) (10.8675, 36.2966) (10.8712, 36.3735) (10.8743, 36.4506) (10.8769, 36.5277) (10.879, 36.605) (10.8805, 36.6823) (10.8814, 36.7598) (10.8817, 36.8374) (10.8814, 36.9151) (10.8806, 36.9928) (10.8792, 37.0707) (10.8772, 37.1487) (10.8748, 37.2267) (10.8719, 37.3048) (10.8685, 37.383) (10.8646, 37.4612) (10.8603, 37.5396) (10.8554, 37.618) (10.8501, 37.6964) (10.8443, 37.7749) (10.838, 37.8535) (10.8313, 37.9322) (10.8242, 38.0109) (10.8166, 38.0896) (10.8086, 38.1684) (10.8001, 38.2473) (10.7912, 38.3262) (10.7819, 38.4051) (10.7721, 38.4841) (10.762, 38.5631) (10.7514, 38.6422) (10.7404, 38.7213) (10.729, 38.8005) (10.7172, 38.8796) (10.705, 38.9589) (10.6924, 39.0381) (10.6794, 39.1174) (10.666, 39.1967) (10.6523, 39.276) (10.6381, 39.3554) (10.6236, 39.4347) (10.6087, 39.5142) (10.5934, 39.5936) (10.5777, 39.673) (10.5617, 39.7525) (10.5453, 39.832) (10.5285, 39.9115) (10.5113, 39.991) (10.4938, 40.0705) (10.4759, 40.1501) (10.4577, 40.2296) (10.4391, 40.3092) (10.4202, 40.3887) (10.4009, 40.4683) (10.3812, 40.5479) (10.3652, 40.6116) (10.3531, 40.6593) (10.3449, 40.6912) (10.3408, 40.7071) knots 0 0 0 0 0 0 0.01428571 0.02857143 0.04285714 0.05714286 0.07142857 0.08571429 0.1 0.11428571 0.12857143 0.14285714 0.15714286 0.17142857 0.18571429 0.2 0.21428571 0.22857143 0.24285714 0.25714286 0.27142857 0.28571429 0.3 0.31428571 0.32857143 0.34285714 0.35714286 0.37142857 0.38571429 0.4 0.41428571 0.42857143 0.44285714 0.45714286 0.47142857 0.48571429 0.5 0.51428571 0.52857143 0.54285714 0.55714286 0.57142857 0.58571429 0.6 0.61428571 0.62857143 0.64285714 0.65714286 0.67142857 0.68571429 0.7 0.71428571 0.72857143 0.74285714 0.75714286 0.77142857 0.78571429 0.8 0.81428571 0.82857143 0.84285714 0.85714286 0.87142857 0.88571429 0.9 0.91428571 0.92857143 0.94285714 0.95714286 0.97142857 0.98571429 1 1 1 1 1 1
  arc A17 (10.3408, 40.7071) -> (8.3454, 41.1625) centre (0, 0) ccw
  spline S9 degree 5 poles (5.6283, 36.4034) (5.6307, 36.4184) (5.6357, 36.4483) (5.6442, 36.4929) (5.6577, 36.552) (5.6772, 36.6252) (5.6988, 36.698) (5.7216, 36.7706) (5.7451, 36.8431) (5.7691, 36.9154) (5.7935, 36.9877) (5.8186, 37.0598) (5.8445, 37.1318) (5.8713, 37.2035) (5.8991, 37.275) (5.9277, 37.3463) (5.9572, 37.4173) (5.9873, 37.4883) (6.0179, 37.559) (6.049, 37.6297) (6.0807, 37.7002) (6.1129, 37.7705) (6.1457, 37.8407) (6.1791, 37.9107) (6.213, 37.9806) (6.2475, 38.0503) (6.2826, 38.1198) (6.3182, 38.1892) (6.3542, 38.2585) (6.3907, 38.3276) (6.4277, 38.3966) (6.4651, 38.4654) (6.503, 38.5341) (6.5414, 38.6026) (6.5803, 38.671) (6.6196, 38.7392) (6.6593, 38.8073) (6.6995, 38.8752) (6.74, 38.943) (6.7811, 39.0107) (6.8225, 39.0782) (6.8643, 39.1456) (6.9066, 39.2128) (6.9492, 39.2799) (6.9923, 39.3468) (7.0357, 39.4136) (7.0796, 39.4803) (7.1238, 39.5468) (7.1684, 39.6131) (7.2134, 39.6794) (7.2587, 39.7454) (7.3045, 39.8114) (7.3506, 39.8772) (7.397, 39.9428) (7.4438, 40.0083) (7.491, 40.0737) (7.5386, 40.1389) (7.5865, 40.204) (7.6347, 40.2689) (7.6833, 40.3337) (7.7322, 40.3983) (7.7815, 40.4628) (7.8311, 40.5271) (7.8811, 40.5913) (7.9313, 40.6554) (7.982, 40.7193) (8.0329, 40.7831) (8.0842, 40.8467) (8.1358, 40.9101) (8.1877, 40.9735) (8.2399, 41.0366) (8.282, 41.0871) (8.3136, 41.1248) (8.3348, 41.15) (8.3454, 41.1625) knots 0 0 0 0 0 0 0.01428571 0.02857143 0.04285714 0.05714286 0.07142857 0.08571429 0.1 0.11428571 0.12857143 0.14285714 0.15714286 0.17142857 0.18571429 0.2 0.21428571 0.22857143 0.24285714 0.25714286 0.27142857 0.28571429 0.3 0.31428571 0.32857143 0.34285714 0.35714286 0.37142857 0.38571429 0.4 0.41428571 0.42857143 0.44285714 0.45714286 0.47142857 0.48571429 0.5 0.51428571 0.52857143 0.54285714 0.55714286 0.57142857 0.58571429 0.6 0.61428571 0.62857143 0.64285714 0.65714286 0.67142857 0.68571429 0.7 0.71428571 0.72857143 0.74285714 0.75714286 0.77142857 0.78571429 0.8 0.81428571 0.82857143 0.84285714 0.85714286 0.87142857 0.88571429 0.9 0.91428571 0.92857143 0.94285714 0.95714286 0.97142857 0.98571429 1 1 1 1 1 1
  line L9 (5.6283, 36.4034) -> (5.619, 36.3431)
  arc A18 (4.5049, 35.5045) -> (5.619, 36.3431) centre (4.6308, 36.4966) ccw
  arc A19 (4.5049, 35.5045) -> (3.5085, 35.6168) centre (0, 0) ccw
  arc A20 (2.609, 36.6823) -> (3.5085, 35.6168) centre (3.6066, 36.612) ccw
  line L10 (2.609, 36.6823) -> (2.6133, 36.7431)
  spline S10 degree 5 poles (2.6133, 36.7431) (2.6144, 36.7583) (2.6161, 36.7885) (2.6177, 36.8339) (2.6178, 36.8945) (2.615, 36.9702) (2.6101, 37.0461) (2.6041, 37.1219) (2.5973, 37.1978) (2.59, 37.2736) (2.5823, 37.3495) (2.5739, 37.4254) (2.5647, 37.5013) (2.5545, 37.5772) (2.5433, 37.6531) (2.5312, 37.7289) (2.5183, 37.8048) (2.5048, 37.8806) (2.4907, 37.9564) (2.476, 38.0322) (2.4608, 38.108) (2.4451, 38.1838) (2.4287, 38.2595) (2.4118, 38.3352) (2.3942, 38.4109) (2.3761, 38.4865) (2.3574, 38.5621) (2.3382, 38.6377) (2.3184, 38.7132) (2.2982, 38.7887) (2.2775, 38.8642) (2.2563, 38.9396) (2.2346, 39.015) (2.2125, 39.0904) (2.1898, 39.1657) (2.1667, 39.2409) (2.1431, 39.3162) (2.1191, 39.3913) (2.0946, 39.4665) (2.0697, 39.5415) (2.0443, 39.6166) (2.0185, 39.6916) (1.9923, 39.7665) (1.9656, 39.8414) (1.9385, 39.9162) (1.911, 39.991) (1.8831, 40.0658) (1.8548, 40.1405) (1.8261, 40.2151) (1.797, 40.2896) (1.7675, 40.3642) (1.7375, 40.4386) (1.7072, 40.513) (1.6765, 40.5874) (1.6455, 40.6616) (1.614, 40.7359) (1.5822, 40.81) (1.55, 40.8841) (1.5174, 40.9581) (1.4844, 41.0321) (1.4511, 41.106) (1.4174, 41.1798) (1.3834, 41.2536) (1.349, 41.3273) (1.3142, 41.401) (1.2791, 41.4745) (1.2436, 41.548) (1.2078, 41.6215) (1.1716, 41.6948) (1.1351, 41.7681) (1.0982, 41.8413) (1.0684, 41.8998) (1.0459, 41.9437) (1.0309, 41.9729) (1.0233, 41.9875) knots 0 0 0 0 0 0 0.01428571 0.02857143 0.04285714 0.05714286 0.07142857 0.08571429 0.1 0.11428571 0.12857143 0.14285714 0.15714286 0.17142857 0.18571429 0.2 0.21428571 0.22857143 0.24285714 0.25714286 0.27142857 0.28571429 0.3 0.31428571 0.32857143 0.34285714 0.35714286 0.37142857 0.38571429 0.4 0.41428571 0.42857143 0.44285714 0.45714286 0.47142857 0.48571429 0.5 0.51428571 0.52857143 0.54285714 0.55714286 0.57142857 0.58571429 0.6 0.61428571 0.62857143 0.64285714 0.65714286 0.67142857 0.68571429 0.7 0.71428571 0.72857143 0.74285714 0.75714286 0.77142857 0.78571429 0.8 0.81428571 0.82857143 0.84285714 0.85714286 0.87142857 0.88571429 0.9 0.91428571 0.92857143 0.94285714 0.95714286 0.97142857 0.98571429 1 1 1 1 1 1
  arc A21 (1.0233, 41.9875) -> (-1.0233, 41.9875) centre (0, 0) ccw
  spline S11 degree 5 poles (-2.6133, 36.7431) (-2.6144, 36.7583) (-2.6161, 36.7885) (-2.6177, 36.8339) (-2.6178, 36.8945) (-2.615, 36.9702) (-2.6101, 37.0461) (-2.6041, 37.1219) (-2.5973, 37.1978) (-2.59, 37.2736) (-2.5823, 37.3495) (-2.5739, 37.4254) (-2.5647, 37.5013) (-2.5545, 37.5772) (-2.5433, 37.6531) (-2.5312, 37.7289) (-2.5183, 37.8048) (-2.5048, 37.8806) (-2.4907, 37.9564) (-2.476, 38.0322) (-2.4608, 38.108) (-2.4451, 38.1838) (-2.4287, 38.2595) (-2.4118, 38.3352) (-2.3942, 38.4109) (-2.3761, 38.4865) (-2.3574, 38.5621) (-2.3382, 38.6377) (-2.3184, 38.7132) (-2.2982, 38.7887) (-2.2775, 38.8642) (-2.2563, 38.9396) (-2.2346, 39.015) (-2.2125, 39.0904) (-2.1898, 39.1657) (-2.1667, 39.2409) (-2.1431, 39.3162) (-2.1191, 39.3913) (-2.0946, 39.4665) (-2.0697, 39.5415) (-2.0443, 39.6166) (-2.0185, 39.6916) (-1.9923, 39.7665) (-1.9656, 39.8414) (-1.9385, 39.9162) (-1.911, 39.991) (-1.8831, 40.0658) (-1.8548, 40.1405) (-1.8261, 40.2151) (-1.797, 40.2896) (-1.7675, 40.3642) (-1.7375, 40.4386) (-1.7072, 40.513) (-1.6765, 40.5874) (-1.6455, 40.6616) (-1.614, 40.7359) (-1.5822, 40.81) (-1.55, 40.8841) (-1.5174, 40.9581) (-1.4844, 41.0321) (-1.4511, 41.106) (-1.4174, 41.1798) (-1.3834, 41.2536) (-1.349, 41.3273) (-1.3142, 41.401) (-1.2791, 41.4745) (-1.2436, 41.548) (-1.2078, 41.6215) (-1.1716, 41.6948) (-1.1351, 41.7681) (-1.0982, 41.8413) (-1.0684, 41.8998) (-1.0459, 41.9437) (-1.0309, 41.9729) (-1.0233, 41.9875) knots 0 0 0 0 0 0 0.01428571 0.02857143 0.04285714 0.05714286 0.07142857 0.08571429 0.1 0.11428571 0.12857143 0.14285714 0.15714286 0.17142857 0.18571429 0.2 0.21428571 0.22857143 0.24285714 0.25714286 0.27142857 0.28571429 0.3 0.31428571 0.32857143 0.34285714 0.35714286 0.37142857 0.38571429 0.4 0.41428571 0.42857143 0.44285714 0.45714286 0.47142857 0.48571429 0.5 0.51428571 0.52857143 0.54285714 0.55714286 0.57142857 0.58571429 0.6 0.61428571 0.62857143 0.64285714 0.65714286 0.67142857 0.68571429 0.7 0.71428571 0.72857143 0.74285714 0.75714286 0.77142857 0.78571429 0.8 0.81428571 0.82857143 0.84285714 0.85714286 0.87142857 0.88571429 0.9 0.91428571 0.92857143 0.94285714 0.95714286 0.97142857 0.98571429 1 1 1 1 1 1
  line L11 (-2.6133, 36.7431) -> (-2.609, 36.6823)
  arc A22 (-3.5085, 35.6168) -> (-2.609, 36.6823) centre (-3.6066, 36.612) ccw
  arc A23 (-3.5085, 35.6168) -> (-4.5049, 35.5045) centre (0, 0) ccw
  arc A24 (-5.619, 36.3431) -> (-4.5049, 35.5045) centre (-4.6308, 36.4966) ccw
  line L12 (-5.619, 36.3431) -> (-5.6283, 36.4034)
  spline S12 degree 5 poles (-5.6283, 36.4034) (-5.6307, 36.4184) (-5.6357, 36.4483) (-5.6442, 36.4929) (-5.6577, 36.552) (-5.6772, 36.6252) (-5.6988, 36.698) (-5.7216, 36.7706) (-5.7451, 36.8431) (-5.7691, 36.9154) (-5.7935, 36.9877) (-5.8186, 37.0598) (-5.8445, 37.1318) (-5.8713, 37.2035) (-5.8991, 37.275) (-5.9277, 37.3463) (-5.9572, 37.4173) (-5.9873, 37.4883) (-6.0179, 37.559) (-6.049, 37.6297) (-6.0807, 37.7002) (-6.1129, 37.7705) (-6.1457, 37.8407) (-6.1791, 37.9107) (-6.213, 37.9806) (-6.2475, 38.0503) (-6.2826, 38.1198) (-6.3182, 38.1892) (-6.3542, 38.2585) (-6.3907, 38.3276) (-6.4277, 38.3966) (-6.4651, 38.4654) (-6.503, 38.5341) (-6.5414, 38.6026) (-6.5803, 38.671) (-6.6196, 38.7392) (-6.6593, 38.8073) (-6.6995, 38.8752) (-6.74, 38.943) (-6.7811, 39.0107) (-6.8225, 39.0782) (-6.8643, 39.1456) (-6.9066, 39.2128) (-6.9492, 39.2799) (-6.9923, 39.3468) (-7.0357, 39.4136) (-7.0796, 39.4803) (-7.1238, 39.5468) (-7.1684, 39.6131) (-7.2134, 39.6794) (-7.2587, 39.7454) (-7.3045, 39.8114) (-7.3506, 39.8772) (-7.397, 39.9428) (-7.4438, 40.0083) (-7.491, 40.0737) (-7.5386, 40.1389) (-7.5865, 40.204) (-7.6347, 40.2689) (-7.6833, 40.3337) (-7.7322, 40.3983) (-7.7815, 40.4628) (-7.8311, 40.5271) (-7.8811, 40.5913) (-7.9313, 40.6554) (-7.982, 40.7193) (-8.0329, 40.7831) (-8.0842, 40.8467) (-8.1358, 40.9101) (-8.1877, 40.9735) (-8.2399, 41.0366) (-8.282, 41.0871) (-8.3136, 41.1248) (-8.3348, 41.15) (-8.3454, 41.1625) knots 0 0 0 0 0 0 0.01428571 0.02857143 0.04285714 0.05714286 0.07142857 0.08571429 0.1 0.11428571 0.12857143 0.14285714 0.15714286 0.17142857 0.18571429 0.2 0.21428571 0.22857143 0.24285714 0.25714286 0.27142857 0.28571429 0.3 0.31428571 0.32857143 0.34285714 0.35714286 0.37142857 0.38571429 0.4 0.41428571 0.42857143 0.44285714 0.45714286 0.47142857 0.48571429 0.5 0.51428571 0.52857143 0.54285714 0.55714286 0.57142857 0.58571429 0.6 0.61428571 0.62857143 0.64285714 0.65714286 0.67142857 0.68571429 0.7 0.71428571 0.72857143 0.74285714 0.75714286 0.77142857 0.78571429 0.8 0.81428571 0.82857143 0.84285714 0.85714286 0.87142857 0.88571429 0.9 0.91428571 0.92857143 0.94285714 0.95714286 0.97142857 0.98571429 1 1 1 1 1 1
  arc A25 (-8.3454, 41.1625) -> (-10.3408, 40.7071) centre (0, 0) ccw
  spline S13 degree 5 poles (-10.7239, 35.2404) (-10.7283, 35.2549) (-10.7368, 35.284) (-10.7484, 35.3279) (-10.7619, 35.3869) (-10.7761, 35.4614) (-10.7882, 35.5364) (-10.7992, 35.6117) (-10.8094, 35.6872) (-10.8192, 35.7628) (-10.8286, 35.8385) (-10.8373, 35.9144) (-10.8452, 35.9904) (-10.8522, 36.0666) (-10.8581, 36.1431) (-10.8632, 36.2198) (-10.8675, 36.2966) (-10.8712, 36.3735) (-10.8743, 36.4506) (-10.8769, 36.5277) (-10.879, 36.605) (-10.8805, 36.6823) (-10.8814, 36.7598) (-10.8817, 36.8374) (-10.8814, 36.9151) (-10.8806, 36.9928) (-10.8792, 37.0707) (-10.8772, 37.1487) (-10.8748, 37.2267) (-10.8719, 37.3048) (-10.8685, 37.383) (-10.8646, 37.4612) (-10.8603, 37.5396) (-10.8554, 37.618) (-10.8501, 37.6964) (-10.8443, 37.7749) (-10.838, 37.8535) (-10.8313, 37.9322) (-10.8242, 38.0109) (-10.8166, 38.0896) (-10.8086, 38.1684) (-10.8001, 38.2473) (-10.7912, 38.3262) (-10.7819, 38.4051) (-10.7721, 38.4841) (-10.762, 38.5631) (-10.7514, 38.6422) (-10.7404, 38.7213) (-10.729, 38.8005) (-10.7172, 38.8796) (-10.705, 38.9589) (-10.6924, 39.0381) (-10.6794, 39.1174) (-10.666, 39.1967) (-10.6523, 39.276) (-10.6381, 39.3554) (-10.6236, 39.4347) (-10.6087, 39.5142) (-10.5934, 39.5936) (-10.5777, 39.673) (-10.5617, 39.7525) (-10.5453, 39.832) (-10.5285, 39.9115) (-10.5113, 39.991) (-10.4938, 40.0705) (-10.4759, 40.1501) (-10.4577, 40.2296) (-10.4391, 40.3092) (-10.4202, 40.3887) (-10.4009, 40.4683) (-10.3812, 40.5479) (-10.3652, 40.6116) (-10.3531, 40.6593) (-10.3449, 40.6912) (-10.3408, 40.7071) knots 0 0 0 0 0 0 0.01428571 0.02857143 0.04285714 0.05714286 0.07142857 0.08571429 0.1 0.11428571 0.12857143 0.14285714 0.15714286 0.17142857 0.18571429 0.2 0.21428571 0.22857143 0.24285714 0.25714286 0.27142857 0.28571429 0.3 0.31428571 0.32857143 0.34285714 0.35714286 0.37142857 0.38571429 0.4 0.41428571 0.42857143 0.44285714 0.45714286 0.47142857 0.48571429 0.5 0.51428571 0.52857143 0.54285714 0.55714286 0.57142857 0.58571429 0.6 0.61428571 0.62857143 0.64285714 0.65714286 0.67142857 0.68571429 0.7 0.71428571 0.72857143 0.74285714 0.75714286 0.77142857 0.78571429 0.8 0.81428571 0.82857143 0.84285714 0.85714286 0.87142857 0.88571429 0.9 0.91428571 0.92857143 0.94285714 0.95714286 0.97142857 0.98571429 1 1 1 1 1 1
  line L13 (-10.7239, 35.2404) -> (-10.7062, 35.182)
  arc A26 (-11.346, 33.9431) -> (-10.7062, 35.182) centre (-11.6631, 34.8915) ccw
  arc A27 (-11.346, 33.9431) -> (-12.2925, 33.6119) centre (0, 0) ccw
  arc A28 (-13.5652, 34.1816) -> (-12.2925, 33.6119) centre (-12.636, 34.5511) ccw
  line L14 (-13.5652, 34.1816) -> (-13.5877, 34.2383)
  spline S14 degree 5 poles (-13.5877, 34.2383) (-13.5933, 34.2524) (-13.6049, 34.2804) (-13.6232, 34.322) (-13.6494, 34.3766) (-13.6848, 34.4436) (-13.722, 34.5098) (-13.7604, 34.5755) (-13.7995, 34.6409) (-13.8389, 34.7062) (-13.8788, 34.7712) (-13.9193, 34.8359) (-13.9605, 34.9003) (-14.0026, 34.9642) (-14.0456, 35.0278) (-14.0894, 35.0909) (-14.134, 35.1536) (-14.1791, 35.2161) (-14.2247, 35.2782) (-14.2708, 35.3402) (-14.3173, 35.4019) (-14.3644, 35.4633) (-14.412, 35.5244) (-14.4601, 35.5852) (-14.5087, 35.6458) (-14.5579, 35.7061) (-14.6075, 35.7661) (-14.6576, 35.8258) (-14.7082, 35.8853) (-14.7592, 35.9446) (-14.8106, 36.0036) (-14.8624, 36.0624) (-14.9146, 36.1209) (-14.9673, 36.1791) (-15.0204, 36.2372) (-15.0739, 36.295) (-15.1278, 36.3525) (-15.182, 36.4098) (-15.2367, 36.4669) (-15.2917, 36.5237) (-15.3472, 36.5803) (-15.4029, 36.6367) (-15.4591, 36.6928) (-15.5156, 36.7487) (-15.5725, 36.8044) (-15.6297, 36.8598) (-15.6872, 36.9151) (-15.7452, 36.9701) (-15.8034, 37.0248) (-15.862, 37.0794) (-15.9209, 37.1337) (-15.9802, 37.1878) (-16.0398, 37.2417) (-16.0997, 37.2954) (-16.1599, 37.3488) (-16.2204, 37.402) (-16.2813, 37.455) (-16.3425, 37.5078) (-16.404, 37.5604) (-16.4657, 37.6127) (-16.5278, 37.6648) (-16.5902, 37.7168) (-16.6529, 37.7684) (-16.7159, 37.8199) (-16.7792, 37.8712) (-16.8427, 37.9222) (-16.9066, 37.9731) (-16.9707, 38.0237) (-17.0352, 38.0741) (-17.0999, 38.1243) (-17.1648, 38.1742) (-17.2171, 38.214) (-17.2563, 38.2438) (-17.2826, 38.2636) (-17.2957, 38.2735) knots 0 0 0 0 0 0 0.01428571 0.02857143 0.04285714 0.05714286 0.07142857 0.08571429 0.1 0.11428571 0.12857143 0.14285714 0.15714286 0.17142857 0.18571429 0.2 0.21428571 0.22857143 0.24285714 0.25714286 0.27142857 0.28571429 0.3 0.31428571 0.32857143 0.34285714 0.35714286 0.37142857 0.38571429 0.4 0.41428571 0.42857143 0.44285714 0.45714286 0.47142857 0.48571429 0.5 0.51428571 0.52857143 0.54285714 0.55714286 0.57142857 0.58571429 0.6 0.61428571 0.62857143 0.64285714 0.65714286 0.67142857 0.68571429 0.7 0.71428571 0.72857143 0.74285714 0.75714286 0.77142857 0.78571429 0.8 0.81428571 0.82857143 0.84285714 0.85714286 0.87142857 0.88571429 0.9 0.91428571 0.92857143 0.94285714 0.95714286 0.97142857 0.98571429 1 1 1 1 1 1
  arc A29 (-17.2957, 38.2735) -> (-19.1397, 37.3855) centre (0, 0) ccw